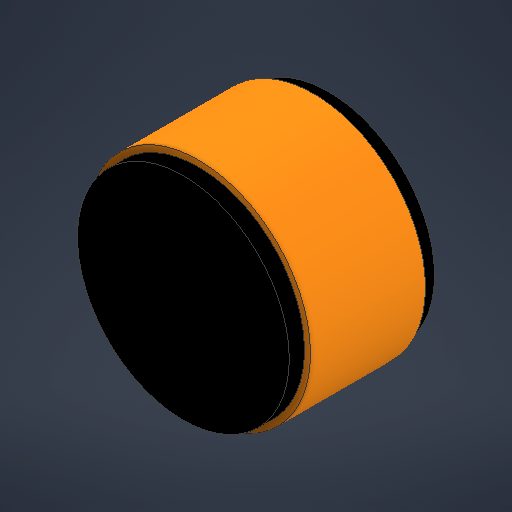
# Autodesk Inventor part: 35mm_wheel
Saved by Autodesk Inventor 2026.3 (Build 303398000, 398)
## iProperties
Created: 2026-07-18
Part Number: 35mm_wheel
Material: Generic
Document SubType Name: Modeling
Designer: nose
Density: 1 g/cm^3
Appearance: Default
Author: nose
Autodesk Inventor part; units mm, degrees
ref_plane "YZ Plane" through (0, 0, 0) normal (1, 0, 0) x (0, 1, 0)
ref_plane "XZ Plane" through (0, 0, 0) normal (0, 1, 0) x (-1, 0, 0)
sketch "Sketch1" plane through (0, 0, 0) normal (0, 0, 1) x (1, 0, 0)
  circle A0 centre (0, 0) radius 17.5
  dimension "d0" = 35
  constraints: 1 centre point, 1 coincident
  measures "d0" diameter of A0
extrude "wheel" add sketch "Sketch1" along normal blind 24
sketch "Sketch2" plane through (0, 0, 0) normal (0, 0, -1) x (-1, 0, 0)
  circle A0 centre (0, 0) radius 17.5 projected
  circle A1 centre (0, 0) radius 1.5
  dimension "d3" = 3
  constraints: 1 centre point, 1 coincident
  measures "d3" diameter of A1
extrude "sharft" cut sketch "Sketch2" against normal blind 12 contours A1
ref_plane "half_plane" through (0, 0, 12) normal (0, 0, 1) x (1, 0, 0)
sketch "Sketch3" plane through (0, 0, 12) normal (0, 0, 1) x (1, 0, 0)
  circle A0 centre (0, 0) radius 1.5 projected
  circle A1 centre (0, 0) radius 18.5
  dimension "d7" = 37
  constraints: 1 centre point, 1 coincident
  measures "d7" diameter of A1
extrude "Extrusion3" add sketch "Sketch3" along normal mid plane 19
equation "\"d0\" = wheel_dia"
equation "\"d1\" = wheel_width"
equation "\"d3\" = wheel_sharft"
equation "\"d4\" = 0.5 * wheel_width"
equation "\"wheel_dia\" = 35"
equation "\"wheel_width\" = 24"
equation "\"wheel_sharft\" = 3"
equation "\"d6\" = 0.5 * wheel_width"
body "Solid1"
